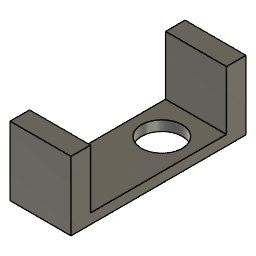
Servo Mounting (Autodesk Fusion 360 design; units mm, degrees)
Autodesk Fusion 360 part; units mm, degrees
sketch "Sketch1" plane through (0, 0, 0) normal (0, 0, 1) x (1, 0, 0)
  line L0 (0, 0) -> (18.9992, 0)
  line L1 (18.9992, 0) -> (18.9992, 54.5084)
  line L2 (18.9992, 54.5084) -> (0, 54.5084)
  line L3 (0, 54.5084) -> (0, 0)
  line L4 (9.4996, 54.5084) -> (9.4996, 37.7952)
  circle A0 centre (9.4996, 37.7952) radius 6.35
  dimension "d1" = 18.9992
  dimension "d2" = 54.5084
  dimension "d3" = 16.7132
  dimension "d4" = 12.7
  constraint horizontal L0
  constraint vertical L1
  constraint horizontal L2
  constraint vertical L3
  constraint coincident L0.start L3.end
  constraint midpoint L2 L4.start
  constraint perpendicular L2 L4
  constraint coincident L4.end A0.centre
  measures "d1" distance of L0.start L0.end
  measures "d2" distance of L0.start L2.end
  measures "d3" distance of L4.start L4.end
  measures "d4" diameter of A0
extrude "Extrude1" add sketch "Sketch1" along normal blind 3.175
sketch "Sketch2" plane through (0, 0, 3.175) normal (0, 0, 1) x (-1, 0, 0)
  circle A0 centre (-9.4996, -37.7952) radius 6.35
  line L0 (0, -54.5084) -> (0, 0)
  line L1 (0, 0) -> (-18.9992, 0)
  line L2 (-18.9992, 0) -> (-18.9992, -54.5084)
  line L3 (-18.9992, -54.5084) -> (0, -54.5084)
  line L4 (0, -54.5084) -> (-19.6618, -54.5084)
  line L5 (-19.6618, -48.4124) -> (0, -48.4124)
  line L6 (0, -48.4124) -> (0, -54.5084)
  line L7 (0, 0) -> (-18.9992, 0)
  line L8 (-18.9992, 0) -> (-18.9992, -6.096)
  line L9 (-18.9992, -6.096) -> (0, -6.096)
  line L10 (0, -6.096) -> (0, 0)
  line L11 (0, -54.5084) -> (-18.9992, -54.5084)
  line L12 (-18.9992, -54.5084) -> (-18.9992, -48.4124)
  line L13 (-18.9992, -48.4124) -> (0, -48.4124)
  line L14 (0, -48.4124) -> (0, -54.5084)
  dimension "d7" = 6.096
  dimension "d8" = 6.096
  constraint horizontal L4
  constraint horizontal L5
  constraint vertical L6
  constraint coincident L0.start L3.end
  constraint horizontal L7
  constraint vertical L8
  constraint horizontal L9
  constraint vertical L10
  constraint coincident L0.end L1.start
  constraint horizontal L11
  constraint vertical L12
  constraint horizontal L13
  constraint vertical L14
  constraint coincident L5 L12.end
  constraint coincident L2 L12.end
  measures "d7" distance of L0.start L5.end
  measures "d8" distance of L0.end L9.end
extrude "Extrude2" add sketch "Sketch2" along normal blind 18.288 contours L0 L2 L3 L4 L5 L6 L11 L12 L13 L14 | L0 L1 L2 L7 L8 L9 L10
